macropad_enclosure_iteration1 (Autodesk Fusion 360 design; units mm, degrees)
part number: 2026-10-12-15-45-26-429
Autodesk Fusion 360 part; units mm, degrees
sketch "Upper shell side profile" plane through (0, 0, 0) normal (1, 0, 0) x (0, 0, -1)
  line L0 (-2, 0) -> (-2, 115)
  line L1 (-2, 115) -> (-32.0612, 115)
  line L2 (-32.0612, 115) -> (-22, 0)
  line L3 (-22, 0) -> (-2, 0)
  dimension "d39" = 2
  dimension "d40" = 115
  dimension "d41" = 30.0612
  dimension "d42" = 20
  constraint vertical L0
  constraint horizontal L1
  constraint horizontal L3
  constraint horizontal origin L0.start
  measures "d39" horizontal distance of origin L0.start
  measures "d40" distance of L0.start L0.end
  measures "d41" distance of L0.end L1.end
  measures "d42" distance of L0.start L2.end
extrude "Upper shell wedge" add sketch "Upper shell side profile" along normal blind 80 makes body 1
shell "Open-bottom exterior shell" thickness 2.4 removed faces 1 at (53.3333, 38.3333, 2) on bodies 1
ref_plane "WorkPlane1" through (12.125, 0, 0) normal (0, -0.087156, 0.996195) x (1, 0, 0)
ref_plane "WorkPlane2" through (12.125, -1.9101, 21.8329) normal (0, -0.087156, 0.996195) x (1, 0, 0)
ref_plane "WorkPlane3" through (12.125, -1.6661, 19.0435) normal (0, -0.087156, 0.996195) x (1, 0, 0)
sketch "Middle carrier outline" plane through (0, -1.6661, 19.0435) normal (0, -0.087156, 0.996195) x (1, 0, 0)
  line L0 (2.8, 4.4832) -> (77.2, 4.4832)
  line L1 (77.2, 4.4832) -> (77.2, 114.1698)
  line L2 (77.2, 114.1698) -> (2.8, 114.1698)
  line L3 (2.8, 114.1698) -> (2.8, 4.4832)
  dimension "d52" = 2.8
  dimension "d53" = 4.4832
  dimension "d54" = 74.4
  dimension "d55" = 109.6867
  constraint horizontal L0
  constraint vertical L1
  constraint horizontal L2
  constraint vertical L3
  measures "d52" horizontal distance of origin L0.start
  measures "d53" vertical distance of origin L0.start
  measures "d54" distance of L0.start L0.end
  measures "d55" distance of L0.end L1.end
extrude "Middle carrier plate" add sketch "Middle carrier outline" against normal blind 1.5 separate body makes body 2
sketch "Carrier rear access opening" plane through (0, -1.6661, 19.0435) normal (0, -0.087156, 0.996195) x (1, 0, 0)
  line L0 (6.8, 62.6371) -> (73.2, 62.6371)
  line L1 (73.2, 62.6371) -> (73.2, 110.1698)
  line L2 (73.2, 110.1698) -> (6.8, 110.1698)
  line L3 (6.8, 110.1698) -> (6.8, 62.6371)
  dimension "d58" = 6.8
  dimension "d59" = 62.6371
  dimension "d60" = 66.4
  dimension "d61" = 47.5327
  constraint horizontal L0
  constraint vertical L1
  constraint horizontal L2
  constraint vertical L3
  measures "d58" horizontal distance of origin L0.start
  measures "d59" vertical distance of origin L0.start
  measures "d60" distance of L0.start L0.end
  measures "d61" distance of L0.end L1.end
extrude "Open carrier electronics bay" cut sketch "Carrier rear access opening" against normal blind 2.5 bodies 2
sketch "SW1 Seat profile" plane through (0, -1.6661, 19.0435) normal (0, -0.087156, 0.996195) x (1, 0, 0)
  line L0 (8.45, 18.8371) -> (22.55, 18.8371)
  line L1 (22.55, 18.8371) -> (22.55, 32.9371)
  line L2 (22.55, 32.9371) -> (8.45, 32.9371)
  line L3 (8.45, 32.9371) -> (8.45, 18.8371)
  dimension "d64" = 8.45
  dimension "d65" = 18.8371
  dimension "d66" = 14.1
  dimension "d67" = 14.1
  constraint horizontal L0
  constraint vertical L1
  constraint horizontal L2
  constraint vertical L3
  measures "d64" horizontal distance of origin L0.start
  measures "d65" vertical distance of origin L0.start
  measures "d66" distance of L0.start L0.end
  measures "d67" distance of L0.end L1.end
extrude "SW1 Seat opening" cut sketch "SW1 Seat profile" against normal blind 2.5 bodies 2
sketch "SW1 Trim profile" plane through (0, -1.9101, 21.8329) normal (0, -0.087156, 0.996195) x (1, 0, 0)
  line L0 (7.4, 17.7871) -> (23.6, 17.7871)
  line L1 (23.6, 17.7871) -> (23.6, 33.9871)
  line L2 (23.6, 33.9871) -> (7.4, 33.9871)
  line L3 (7.4, 33.9871) -> (7.4, 17.7871)
  dimension "d70" = 7.4
  dimension "d71" = 17.7871
  dimension "d72" = 16.2
  dimension "d73" = 16.2
  constraint horizontal L0
  constraint vertical L1
  constraint horizontal L2
  constraint vertical L3
  measures "d70" horizontal distance of origin L0.start
  measures "d71" vertical distance of origin L0.start
  measures "d72" distance of L0.start L0.end
  measures "d73" distance of L0.end L1.end
extrude "SW1 Trim opening" cut sketch "SW1 Trim profile" against normal blind 3.4 bodies 1
sketch "SW2 Seat profile" plane through (0, -1.6661, 19.0435) normal (0, -0.087156, 0.996195) x (1, 0, 0)
  line L0 (32.95, 18.8371) -> (47.05, 18.8371)
  line L1 (47.05, 18.8371) -> (47.05, 32.9371)
  line L2 (47.05, 32.9371) -> (32.95, 32.9371)
  line L3 (32.95, 32.9371) -> (32.95, 18.8371)
  dimension "d76" = 32.95
  dimension "d77" = 18.8371
  dimension "d78" = 14.1
  dimension "d79" = 14.1
  constraint horizontal L0
  constraint vertical L1
  constraint horizontal L2
  constraint vertical L3
  measures "d76" horizontal distance of origin L0.start
  measures "d77" vertical distance of origin L0.start
  measures "d78" distance of L0.start L0.end
  measures "d79" distance of L0.end L1.end
extrude "SW2 Seat opening" cut sketch "SW2 Seat profile" against normal blind 2.5 bodies 2
sketch "SW2 Trim profile" plane through (0, -1.9101, 21.8329) normal (0, -0.087156, 0.996195) x (1, 0, 0)
  line L0 (31.9, 17.7871) -> (48.1, 17.7871)
  line L1 (48.1, 17.7871) -> (48.1, 33.9871)
  line L2 (48.1, 33.9871) -> (31.9, 33.9871)
  line L3 (31.9, 33.9871) -> (31.9, 17.7871)
  dimension "d82" = 31.9
  dimension "d83" = 17.7871
  dimension "d84" = 16.2
  dimension "d85" = 16.2
  constraint horizontal L0
  constraint vertical L1
  constraint horizontal L2
  constraint vertical L3
  measures "d82" horizontal distance of origin L0.start
  measures "d83" vertical distance of origin L0.start
  measures "d84" distance of L0.start L0.end
  measures "d85" distance of L0.end L1.end
extrude "SW2 Trim opening" cut sketch "SW2 Trim profile" against normal blind 3.4 bodies 1
sketch "SW3 Seat profile" plane through (0, -1.6661, 19.0435) normal (0, -0.087156, 0.996195) x (1, 0, 0)
  line L0 (57.45, 18.8371) -> (71.55, 18.8371)
  line L1 (71.55, 18.8371) -> (71.55, 32.9371)
  line L2 (71.55, 32.9371) -> (57.45, 32.9371)
  line L3 (57.45, 32.9371) -> (57.45, 18.8371)
  dimension "d88" = 57.45
  dimension "d89" = 18.8371
  dimension "d90" = 14.1
  dimension "d91" = 14.1
  constraint horizontal L0
  constraint vertical L1
  constraint horizontal L2
  constraint vertical L3
  measures "d88" horizontal distance of origin L0.start
  measures "d89" vertical distance of origin L0.start
  measures "d90" distance of L0.start L0.end
  measures "d91" distance of L0.end L1.end
extrude "SW3 Seat opening" cut sketch "SW3 Seat profile" against normal blind 2.5 bodies 2
sketch "SW3 Trim profile" plane through (0, -1.9101, 21.8329) normal (0, -0.087156, 0.996195) x (1, 0, 0)
  line L0 (56.4, 17.7871) -> (72.6, 17.7871)
  line L1 (72.6, 17.7871) -> (72.6, 33.9871)
  line L2 (72.6, 33.9871) -> (56.4, 33.9871)
  line L3 (56.4, 33.9871) -> (56.4, 17.7871)
  dimension "d94" = 56.4
  dimension "d95" = 17.7871
  dimension "d96" = 16.2
  dimension "d97" = 16.2
  constraint horizontal L0
  constraint vertical L1
  constraint horizontal L2
  constraint vertical L3
  measures "d94" horizontal distance of origin L0.start
  measures "d95" vertical distance of origin L0.start
  measures "d96" distance of L0.start L0.end
  measures "d97" distance of L0.end L1.end
extrude "SW3 Trim opening" cut sketch "SW3 Trim profile" against normal blind 3.4 bodies 1
sketch "SW4 Seat profile" plane through (0, -1.6661, 19.0435) normal (0, -0.087156, 0.996195) x (1, 0, 0)
  line L0 (8.45, 43.3371) -> (22.55, 43.3371)
  line L1 (22.55, 43.3371) -> (22.55, 57.4371)
  line L2 (22.55, 57.4371) -> (8.45, 57.4371)
  line L3 (8.45, 57.4371) -> (8.45, 43.3371)
  dimension "d100" = 8.45
  dimension "d101" = 43.3371
  dimension "d102" = 14.1
  dimension "d103" = 14.1
  constraint horizontal L0
  constraint vertical L1
  constraint horizontal L2
  constraint vertical L3
  measures "d100" horizontal distance of origin L0.start
  measures "d101" vertical distance of origin L0.start
  measures "d102" distance of L0.start L0.end
  measures "d103" distance of L0.end L1.end
extrude "SW4 Seat opening" cut sketch "SW4 Seat profile" against normal blind 2.5 bodies 2
sketch "SW4 Trim profile" plane through (0, -1.9101, 21.8329) normal (0, -0.087156, 0.996195) x (1, 0, 0)
  line L0 (7.4, 42.2871) -> (23.6, 42.2871)
  line L1 (23.6, 42.2871) -> (23.6, 58.4871)
  line L2 (23.6, 58.4871) -> (7.4, 58.4871)
  line L3 (7.4, 58.4871) -> (7.4, 42.2871)
  dimension "d106" = 7.4
  dimension "d107" = 42.2871
  dimension "d108" = 16.2
  dimension "d109" = 16.2
  constraint horizontal L0
  constraint vertical L1
  constraint horizontal L2
  constraint vertical L3
  measures "d106" horizontal distance of origin L0.start
  measures "d107" vertical distance of origin L0.start
  measures "d108" distance of L0.start L0.end
  measures "d109" distance of L0.end L1.end
extrude "SW4 Trim opening" cut sketch "SW4 Trim profile" against normal blind 3.4 bodies 1
sketch "SW5 Seat profile" plane through (0, -1.6661, 19.0435) normal (0, -0.087156, 0.996195) x (1, 0, 0)
  line L0 (32.95, 43.3371) -> (47.05, 43.3371)
  line L1 (47.05, 43.3371) -> (47.05, 57.4371)
  line L2 (47.05, 57.4371) -> (32.95, 57.4371)
  line L3 (32.95, 57.4371) -> (32.95, 43.3371)
  dimension "d112" = 32.95
  dimension "d113" = 43.3371
  dimension "d114" = 14.1
  dimension "d115" = 14.1
  constraint horizontal L0
  constraint vertical L1
  constraint horizontal L2
  constraint vertical L3
  measures "d112" horizontal distance of origin L0.start
  measures "d113" vertical distance of origin L0.start
  measures "d114" distance of L0.start L0.end
  measures "d115" distance of L0.end L1.end
extrude "SW5 Seat opening" cut sketch "SW5 Seat profile" against normal blind 2.5 bodies 2
sketch "SW5 Trim profile" plane through (0, -1.9101, 21.8329) normal (0, -0.087156, 0.996195) x (1, 0, 0)
  line L0 (31.9, 42.2871) -> (48.1, 42.2871)
  line L1 (48.1, 42.2871) -> (48.1, 58.4871)
  line L2 (48.1, 58.4871) -> (31.9, 58.4871)
  line L3 (31.9, 58.4871) -> (31.9, 42.2871)
  dimension "d118" = 31.9
  dimension "d119" = 42.2871
  dimension "d120" = 16.2
  dimension "d121" = 16.2
  constraint horizontal L0
  constraint vertical L1
  constraint horizontal L2
  constraint vertical L3
  measures "d118" horizontal distance of origin L0.start
  measures "d119" vertical distance of origin L0.start
  measures "d120" distance of L0.start L0.end
  measures "d121" distance of L0.end L1.end
extrude "SW5 Trim opening" cut sketch "SW5 Trim profile" against normal blind 3.4 bodies 1
sketch "SW6 Seat profile" plane through (0, -1.6661, 19.0435) normal (0, -0.087156, 0.996195) x (1, 0, 0)
  line L0 (57.45, 43.3371) -> (71.55, 43.3371)
  line L1 (71.55, 43.3371) -> (71.55, 57.4371)
  line L2 (71.55, 57.4371) -> (57.45, 57.4371)
  line L3 (57.45, 57.4371) -> (57.45, 43.3371)
  dimension "d124" = 57.45
  dimension "d125" = 43.3371
  dimension "d126" = 14.1
  dimension "d127" = 14.1
  constraint horizontal L0
  constraint vertical L1
  constraint horizontal L2
  constraint vertical L3
  measures "d124" horizontal distance of origin L0.start
  measures "d125" vertical distance of origin L0.start
  measures "d126" distance of L0.start L0.end
  measures "d127" distance of L0.end L1.end
extrude "SW6 Seat opening" cut sketch "SW6 Seat profile" against normal blind 2.5 bodies 2
sketch "SW6 Trim profile" plane through (0, -1.9101, 21.8329) normal (0, -0.087156, 0.996195) x (1, 0, 0)
  line L0 (56.4, 42.2871) -> (72.6, 42.2871)
  line L1 (72.6, 42.2871) -> (72.6, 58.4871)
  line L2 (72.6, 58.4871) -> (56.4, 58.4871)
  line L3 (56.4, 58.4871) -> (56.4, 42.2871)
  dimension "d130" = 56.4
  dimension "d131" = 42.2871
  dimension "d132" = 16.2
  dimension "d133" = 16.2
  constraint horizontal L0
  constraint vertical L1
  constraint horizontal L2
  constraint vertical L3
  measures "d130" horizontal distance of origin L0.start
  measures "d131" vertical distance of origin L0.start
  measures "d132" distance of L0.start L0.end
  measures "d133" distance of L0.end L1.end
extrude "SW6 Trim opening" cut sketch "SW6 Trim profile" against normal blind 3.4 bodies 1
sketch "LED diffuser opening profile" plane through (0, -1.9101, 21.8329) normal (0, -0.087156, 0.996195) x (1, 0, 0)
  line L0 (6.5, 92.3871) -> (73.5, 92.3871)
  line L1 (73.5, 92.3871) -> (73.5, 102.3871)
  line L2 (73.5, 102.3871) -> (6.5, 102.3871)
  line L3 (6.5, 102.3871) -> (6.5, 92.3871)
  dimension "d136" = 6.5
  dimension "d137" = 92.3871
  dimension "d138" = 67
  dimension "d139" = 10
  constraint horizontal L0
  constraint vertical L1
  constraint horizontal L2
  constraint vertical L3
  measures "d136" horizontal distance of origin L0.start
  measures "d137" vertical distance of origin L0.start
  measures "d138" distance of L0.start L0.end
  measures "d139" distance of L0.end L1.end
extrude "LED diffuser opening" cut sketch "LED diffuser opening profile" against normal blind 3.4 bodies 1
sketch "OLED window profile" plane through (0, -1.9101, 21.8329) normal (0, -0.087156, 0.996195) x (1, 0, 0)
  line L0 (6.5, 66.6371) -> (41, 66.6371)
  line L1 (41, 66.6371) -> (41, 85.1371)
  line L2 (41, 85.1371) -> (6.5, 85.1371)
  line L3 (6.5, 85.1371) -> (6.5, 66.6371)
  dimension "d142" = 6.5
  dimension "d143" = 66.6371
  dimension "d145" = 18.5
  constraint horizontal L0
  constraint vertical L1
  constraint horizontal L2
  constraint vertical L3
  measures "d142" horizontal distance of origin L0.start
  measures "d143" vertical distance of origin L0.start
  measures "d145" distance of L0.end L1.end
extrude "OLED window" cut sketch "OLED window profile" against normal blind 3.4 bodies 1
sketch "Encoder provisional bushing profile" plane through (0, -1.9101, 21.8329) normal (0, -0.087156, 0.996195) x (1, 0, 0)
  circle A0 centre (60.5, 75.8871) radius 3.5
  dimension "d148" = 60.5
  dimension "d149" = 75.8871
  dimension "d150" = 7
  measures "d148" horizontal distance of origin A0.centre
  measures "d149" vertical distance of origin A0.centre
  measures "d150" diameter of A0
extrude "Encoder provisional opening" cut sketch "Encoder provisional bushing profile" against normal blind 3.4 bodies 1
sketch "Bottom cover outline" plane through (0, 0, 0) normal (0, 0, 1) x (1, 0, 0)
  line L0 (0, 0) -> (80, 0)
  line L1 (80, 0) -> (80, 115)
  line L2 (80, 115) -> (0, 115)
  line L3 (0, 115) -> (0, 0)
  dimension "d153" = 80
  dimension "d154" = 115
  constraint horizontal L0
  constraint vertical L1
  constraint horizontal L2
  constraint vertical L3
  constraint coincident L0.start L3.end
  measures "d153" distance of L0.start L0.end
  measures "d154" distance of L0.end L1.end
extrude "Bottom service cover" add sketch "Bottom cover outline" along normal blind 2 separate body makes body 3
sketch "Diffuser flush plug profile" plane through (0, -1.9101, 21.8329) normal (0, -0.087156, 0.996195) x (1, 0, 0)
  line L0 (6.7, 92.5871) -> (73.3, 92.5871)
  line L1 (73.3, 92.5871) -> (73.3, 102.1871)
  line L2 (73.3, 102.1871) -> (6.7, 102.1871)
  line L3 (6.7, 102.1871) -> (6.7, 92.5871)
  dimension "d157" = 6.7
  dimension "d158" = 92.5871
  dimension "d159" = 66.6
  dimension "d160" = 9.6
  constraint horizontal L0
  constraint vertical L1
  constraint horizontal L2
  constraint vertical L3
  measures "d157" horizontal distance of origin L0.start
  measures "d158" vertical distance of origin L0.start
  measures "d159" distance of L0.start L0.end
  measures "d160" distance of L0.end L1.end
extrude "Diffuser flush plug" add sketch "Diffuser flush plug profile" against normal blind 2.4 separate body makes body 4
ref_plane "WorkPlane4" through (12.125, -1.701, 19.442) normal (0, -0.087156, 0.996195) x (1, 0, 0)
sketch "Diffuser retaining flange profile" plane through (0, -1.701, 19.442) normal (0, -0.087156, 0.996195) x (1, 0, 0)
  line L0 (5.2, 91.0871) -> (74.8, 91.0871)
  line L1 (74.8, 91.0871) -> (74.8, 103.6871)
  line L2 (74.8, 103.6871) -> (5.2, 103.6871)
  line L3 (5.2, 103.6871) -> (5.2, 91.0871)
  dimension "d165" = 5.2
  dimension "d166" = 91.0871
  dimension "d167" = 69.6
  dimension "d168" = 12.6
  constraint horizontal L0
  constraint vertical L1
  constraint horizontal L2
  constraint vertical L3
  measures "d165" horizontal distance of origin L0.start
  measures "d166" vertical distance of origin L0.start
  measures "d167" distance of L0.start L0.end
  measures "d168" distance of L0.end L1.end
extrude "Diffuser retaining flange" add sketch "Diffuser retaining flange profile" against normal blind 1 bodies 4
sketch "SW1 keycap envelope" plane through (0, -1.9101, 21.8329) normal (0, -0.087156, 0.996195) x (1, 0, 0)
  line L0 (6.5, 16.8871) -> (24.5, 16.8871) construction
  line L1 (24.5, 16.8871) -> (24.5, 34.8871) construction
  line L2 (24.5, 34.8871) -> (6.5, 34.8871) construction
  line L3 (6.5, 34.8871) -> (6.5, 16.8871) construction
  dimension "d172" = 6.5
  dimension "d173" = 16.8871
  dimension "d174" = 18
  dimension "d175" = 18
  constraint horizontal L0
  constraint vertical L1
  constraint horizontal L2
  constraint vertical L3
  measures "d172" horizontal distance of origin L0.start
  measures "d173" vertical distance of origin L0.start
  measures "d174" distance of L0.start L0.end
  measures "d175" distance of L0.end L1.end
sketch "SW2 keycap envelope" plane through (0, -1.9101, 21.8329) normal (0, -0.087156, 0.996195) x (1, 0, 0)
  line L0 (31, 16.8871) -> (49, 16.8871) construction
  line L1 (49, 16.8871) -> (49, 34.8871) construction
  line L2 (49, 34.8871) -> (31, 34.8871) construction
  line L3 (31, 34.8871) -> (31, 16.8871) construction
  dimension "d176" = 31
  dimension "d177" = 16.8871
  dimension "d178" = 18
  dimension "d179" = 18
  constraint horizontal L0
  constraint vertical L1
  constraint horizontal L2
  constraint vertical L3
  measures "d176" horizontal distance of origin L0.start
  measures "d177" vertical distance of origin L0.start
  measures "d178" distance of L0.start L0.end
  measures "d179" distance of L0.end L1.end
sketch "SW3 keycap envelope" plane through (0, -1.9101, 21.8329) normal (0, -0.087156, 0.996195) x (1, 0, 0)
  line L0 (55.5, 16.8871) -> (73.5, 16.8871) construction
  line L1 (73.5, 16.8871) -> (73.5, 34.8871) construction
  line L2 (73.5, 34.8871) -> (55.5, 34.8871) construction
  line L3 (55.5, 34.8871) -> (55.5, 16.8871) construction
  dimension "d180" = 55.5
  dimension "d181" = 16.8871
  dimension "d182" = 18
  dimension "d183" = 18
  constraint horizontal L0
  constraint vertical L1
  constraint horizontal L2
  constraint vertical L3
  measures "d180" horizontal distance of origin L0.start
  measures "d181" vertical distance of origin L0.start
  measures "d182" distance of L0.start L0.end
  measures "d183" distance of L0.end L1.end
sketch "SW4 keycap envelope" plane through (0, -1.9101, 21.8329) normal (0, -0.087156, 0.996195) x (1, 0, 0)
  line L0 (6.5, 41.3871) -> (24.5, 41.3871) construction
  line L1 (24.5, 41.3871) -> (24.5, 59.3871) construction
  line L2 (24.5, 59.3871) -> (6.5, 59.3871) construction
  line L3 (6.5, 59.3871) -> (6.5, 41.3871) construction
  dimension "d184" = 6.5
  dimension "d185" = 41.3871
  dimension "d186" = 18
  dimension "d187" = 18
  constraint horizontal L0
  constraint vertical L1
  constraint horizontal L2
  constraint vertical L3
  measures "d184" horizontal distance of origin L0.start
  measures "d185" vertical distance of origin L0.start
  measures "d186" distance of L0.start L0.end
  measures "d187" distance of L0.end L1.end
sketch "SW5 keycap envelope" plane through (0, -1.9101, 21.8329) normal (0, -0.087156, 0.996195) x (1, 0, 0)
  line L0 (31, 41.3871) -> (49, 41.3871) construction
  line L1 (49, 41.3871) -> (49, 59.3871) construction
  line L2 (49, 59.3871) -> (31, 59.3871) construction
  line L3 (31, 59.3871) -> (31, 41.3871) construction
  dimension "d188" = 31
  dimension "d189" = 41.3871
  dimension "d190" = 18
  dimension "d191" = 18
  constraint horizontal L0
  constraint vertical L1
  constraint horizontal L2
  constraint vertical L3
  measures "d188" horizontal distance of origin L0.start
  measures "d189" vertical distance of origin L0.start
  measures "d190" distance of L0.start L0.end
  measures "d191" distance of L0.end L1.end
sketch "SW6 keycap envelope" plane through (0, -1.9101, 21.8329) normal (0, -0.087156, 0.996195) x (1, 0, 0)
  line L0 (55.5, 41.3871) -> (73.5, 41.3871) construction
  line L1 (73.5, 41.3871) -> (73.5, 59.3871) construction
  line L2 (73.5, 59.3871) -> (55.5, 59.3871) construction
  line L3 (55.5, 59.3871) -> (55.5, 41.3871) construction
  dimension "d192" = 55.5
  dimension "d193" = 41.3871
  dimension "d194" = 18
  dimension "d195" = 18
  constraint horizontal L0
  constraint vertical L1
  constraint horizontal L2
  constraint vertical L3
  measures "d192" horizontal distance of origin L0.start
  measures "d193" vertical distance of origin L0.start
  measures "d194" distance of L0.start L0.end
  measures "d195" distance of L0.end L1.end
sketch "Encoder knob envelope - provisional diameter" plane through (0, -1.9101, 21.8329) normal (0, -0.087156, 0.996195) x (1, 0, 0)
  circle A0 centre (60.5, 75.8871) radius 10 construction
  dimension "d196" = 60.5
  dimension "d197" = 75.8871
  dimension "d198" = 20
  measures "d196" horizontal distance of origin A0.centre
  measures "d197" vertical distance of origin A0.centre
  measures "d198" diameter of A0
sketch "Diffuser flange carrier pocket profile" plane through (0, -1.6661, 19.0435) normal (0, -0.087156, 0.996195) x (1, 0, 0)
  line L0 (5, 90.8871) -> (75, 90.8871)
  line L1 (75, 90.8871) -> (75, 103.8871)
  line L2 (75, 103.8871) -> (5, 103.8871)
  line L3 (5, 103.8871) -> (5, 90.8871)
  dimension "d200" = 5
  dimension "d201" = 90.8871
  dimension "d202" = 70
  dimension "d203" = 13
  constraint horizontal L0
  constraint vertical L1
  constraint horizontal L2
  constraint vertical L3
  measures "d200" horizontal distance of origin L0.start
  measures "d201" vertical distance of origin L0.start
  measures "d202" distance of L0.start L0.end
  measures "d203" distance of L0.end L1.end
extrude "Diffuser flange carrier recess" cut sketch "Diffuser flange carrier pocket profile" against normal blind 0.8 bodies 2
hidden bodies 1 3
equation "caseWidth = 80 mm" comment "Exterior width"
equation "caseLength = 115 mm" comment "Horizontal front-to-rear footprint"
equation "caseTilt = 5 deg" comment "Rear-up face angle; provisional"
equation "frontHeight = 22 mm" comment "Draft height, to be checked against electronics"
equation "rearHeight = frontHeight + caseLength * tan(caseTilt)" comment "Rear height"
equation "shellWall = 2.4 mm" comment "Draft shell thickness"
equation "bottomThickness = 2 mm" comment "Service cover thickness"
equation "carrierThickness = 1.5 mm" comment "Local switch clip seating thickness"
equation "carrierClearance = 0.4 mm" comment "Draft carrier clearance"
equation "carrierRim = 4 mm" comment "Carrier frame width"
equation "keycapSize = 18 mm" comment "Confirmed square keycap size"
equation "layoutGap = ( caseWidth - 3 * keycapSize ) / 4" comment "Equal visible horizontal gaps"
equation "keyPitch = keycapSize + layoutGap" comment "Equal row and column pitch"
equation "switchOpening = 14.1 mm" comment "Draft opening; coupon verification required"
equation "upperSwitchOpening = 16.2 mm" comment "Draft outer trim clearance"
equation "displayWidth = 34.5 mm" comment "User-supplied window width"
equation "displayHeight = 18.5 mm" comment "User-supplied window height"
equation "encoderKnobDiameter = 20 mm" comment "Placeholder; actual knob diameter required"
equation "encoderHole = 7 mm" comment "User-supplied provisional opening; verify bushing"
equation "ledWidth = 67 mm" comment "User-supplied strip width"
equation "ledHeight = 10 mm" comment "Initial diffuser opening height"
equation "diffuserClearance = 0.2 mm" comment "Per-edge draft fit clearance"
equation "diffuserFlange = 1.5 mm" comment "Retaining flange extension per side"
equation "diffuserFlangeThickness = 1 mm" comment "Retaining flange thickness"
equation "faceLength = caseLength / cos(caseTilt)" comment "Length measured in the inclined face"
equation "faceOriginV = frontHeight * sin(caseTilt)" comment "Inclined sketch origin correction"
equation "controlHeight = max(displayHeight; encoderKnobDiameter)" comment "Visible controls row height"
equation "contentLength = 2 * keycapSize + 3 * layoutGap + controlHeight + ledHeight" comment "Visible layout stack"
equation "verticalMargin = ( faceLength - contentLength ) / 2" comment "Balanced front and rear margins"
equation "keyRowOne = verticalMargin + keycapSize / 2" comment "Front key row center"
equation "keyRowTwo = keyRowOne + keyPitch" comment "Rear key row center"
equation "controlCenter = keyRowTwo + keycapSize / 2 + layoutGap + controlHeight / 2" comment "Display and encoder center"
equation "ledCenter = controlCenter + controlHeight / 2 + layoutGap + ledHeight / 2" comment "LED opening center"
equation "encoderCenterX = ( layoutGap + displayWidth + caseWidth ) / 2" comment "Centered in the area right of the display"
equation "d39 = -( ( 0 ) * ( 0 mm ) + ( -1 ) * ( bottomThickness ) )"
equation "d40 = ( ( 1 ) * ( caseLength ) + ( 0 ) * ( bottomThickness ) ) - ( ( 1 ) * ( 0 mm ) + ( 0 ) * ( bottomThickness ) )"
equation "d41 = -( ( ( 0 ) * ( caseLength ) + ( -1 ) * ( rearHeight ) ) - ( ( 0 ) * ( caseLength ) + ( -1 ) * ( bottomThickness ) ) )"
equation "d42 = ( ( 0 ) * ( 0 mm ) + ( -1 ) * ( bottomThickness ) ) - ( ( 0 ) * ( 0 mm ) + ( -1 ) * ( frontHeight ) )"
equation "d43 = caseWidth"
equation "d45 = shellWall"
equation "d46 = caseTilt"
equation "d48 = frontHeight * cos(caseTilt)"
equation "d50 = -( shellWall + carrierClearance )"
equation "d52 = shellWall + carrierClearance"
equation "d53 = ( ( shellWall + carrierClearance ) / cos(caseTilt) - ( shellWall + carrierClearance ) * tan(caseTilt) ) + faceOriginV"
equation "d54 = ( ( shellWall + carrierClearance ) + ( caseWidth - 2 * ( shellWall + carrierClearance ) ) ) - ( shellWall + carrierClearance )"
equation "d55 = carrierFaceLength"
equation "d56 = -( carrierThickness )"
equation "d58 = ( caseWidth - carrierBayWidth ) / 2"
equation "d59 = ( keyRowTwo + keycapSize / 2 + layoutGap / 2 ) + faceOriginV"
equation "d60 = carrierBayWidth"
equation "d61 = faceLength - ( shellWall + carrierClearance ) / cos(caseTilt) - ( shellWall + carrierClearance + carrierThickness ) * tan(caseTilt) - carrierRim - ( keyRowTwo + keycapSize / 2 + layoutGap / 2 )"
equation "d62 = -( carrierThickness + 1 mm )"
equation "d64 = ( layoutGap + keycapSize / 2 + 0 * keyPitch ) - switchOpening / 2"
equation "d65 = ( ( keyRowOne ) - switchOpening / 2 ) + faceOriginV"
equation "d66 = ( ( ( layoutGap + keycapSize / 2 + 0 * keyPitch ) - switchOpening / 2 ) + ( switchOpening ) ) - ( ( layoutGap + keycapSize / 2 + 0 * keyPitch ) - switchOpening / 2 )"
equation "d67 = ( ( ( ( keyRowOne ) - switchOpening / 2 ) + faceOriginV ) + ( switchOpening ) ) - ( ( ( keyRowOne ) - switchOpening / 2 ) + faceOriginV )"
equation "d68 = -( carrierThickness + 1 mm )"
equation "d70 = ( layoutGap + keycapSize / 2 + 0 * keyPitch ) - upperSwitchOpening / 2"
equation "d71 = ( ( keyRowOne ) - upperSwitchOpening / 2 ) + faceOriginV"
equation "d72 = ( ( ( layoutGap + keycapSize / 2 + 0 * keyPitch ) - upperSwitchOpening / 2 ) + ( upperSwitchOpening ) ) - ( ( layoutGap + keycapSize / 2 + 0 * keyPitch ) - upperSwitchOpening / 2 )"
equation "d73 = ( ( ( ( keyRowOne ) - upperSwitchOpening / 2 ) + faceOriginV ) + ( upperSwitchOpening ) ) - ( ( ( keyRowOne ) - upperSwitchOpening / 2 ) + faceOriginV )"
equation "d74 = -( shellWall + 1 mm )"
equation "d76 = ( layoutGap + keycapSize / 2 + 1 * keyPitch ) - switchOpening / 2"
equation "d77 = ( ( keyRowOne ) - switchOpening / 2 ) + faceOriginV"
equation "d78 = ( ( ( layoutGap + keycapSize / 2 + 1 * keyPitch ) - switchOpening / 2 ) + ( switchOpening ) ) - ( ( layoutGap + keycapSize / 2 + 1 * keyPitch ) - switchOpening / 2 )"
equation "d79 = ( ( ( ( keyRowOne ) - switchOpening / 2 ) + faceOriginV ) + ( switchOpening ) ) - ( ( ( keyRowOne ) - switchOpening / 2 ) + faceOriginV )"
equation "d80 = -( carrierThickness + 1 mm )"
equation "d82 = ( layoutGap + keycapSize / 2 + 1 * keyPitch ) - upperSwitchOpening / 2"
equation "d83 = ( ( keyRowOne ) - upperSwitchOpening / 2 ) + faceOriginV"
equation "d84 = ( ( ( layoutGap + keycapSize / 2 + 1 * keyPitch ) - upperSwitchOpening / 2 ) + ( upperSwitchOpening ) ) - ( ( layoutGap + keycapSize / 2 + 1 * keyPitch ) - upperSwitchOpening / 2 )"
equation "d85 = ( ( ( ( keyRowOne ) - upperSwitchOpening / 2 ) + faceOriginV ) + ( upperSwitchOpening ) ) - ( ( ( keyRowOne ) - upperSwitchOpening / 2 ) + faceOriginV )"
equation "d86 = -( shellWall + 1 mm )"
equation "d88 = ( layoutGap + keycapSize / 2 + 2 * keyPitch ) - switchOpening / 2"
equation "d89 = ( ( keyRowOne ) - switchOpening / 2 ) + faceOriginV"
equation "d90 = ( ( ( layoutGap + keycapSize / 2 + 2 * keyPitch ) - switchOpening / 2 ) + ( switchOpening ) ) - ( ( layoutGap + keycapSize / 2 + 2 * keyPitch ) - switchOpening / 2 )"
equation "d91 = ( ( ( ( keyRowOne ) - switchOpening / 2 ) + faceOriginV ) + ( switchOpening ) ) - ( ( ( keyRowOne ) - switchOpening / 2 ) + faceOriginV )"
equation "d92 = -( carrierThickness + 1 mm )"
equation "d94 = ( layoutGap + keycapSize / 2 + 2 * keyPitch ) - upperSwitchOpening / 2"
equation "d95 = ( ( keyRowOne ) - upperSwitchOpening / 2 ) + faceOriginV"
equation "d96 = ( ( ( layoutGap + keycapSize / 2 + 2 * keyPitch ) - upperSwitchOpening / 2 ) + ( upperSwitchOpening ) ) - ( ( layoutGap + keycapSize / 2 + 2 * keyPitch ) - upperSwitchOpening / 2 )"
equation "d97 = ( ( ( ( keyRowOne ) - upperSwitchOpening / 2 ) + faceOriginV ) + ( upperSwitchOpening ) ) - ( ( ( keyRowOne ) - upperSwitchOpening / 2 ) + faceOriginV )"
equation "d98 = -( shellWall + 1 mm )"
equation "d100 = ( layoutGap + keycapSize / 2 + 0 * keyPitch ) - switchOpening / 2"
equation "d101 = ( ( keyRowTwo ) - switchOpening / 2 ) + faceOriginV"
equation "d102 = ( ( ( layoutGap + keycapSize / 2 + 0 * keyPitch ) - switchOpening / 2 ) + ( switchOpening ) ) - ( ( layoutGap + keycapSize / 2 + 0 * keyPitch ) - switchOpening / 2 )"
equation "d103 = ( ( ( ( keyRowTwo ) - switchOpening / 2 ) + faceOriginV ) + ( switchOpening ) ) - ( ( ( keyRowTwo ) - switchOpening / 2 ) + faceOriginV )"
equation "d104 = -( carrierThickness + 1 mm )"
equation "d106 = ( layoutGap + keycapSize / 2 + 0 * keyPitch ) - upperSwitchOpening / 2"
equation "d107 = ( ( keyRowTwo ) - upperSwitchOpening / 2 ) + faceOriginV"
equation "d108 = ( ( ( layoutGap + keycapSize / 2 + 0 * keyPitch ) - upperSwitchOpening / 2 ) + ( upperSwitchOpening ) ) - ( ( layoutGap + keycapSize / 2 + 0 * keyPitch ) - upperSwitchOpening / 2 )"
equation "d109 = ( ( ( ( keyRowTwo ) - upperSwitchOpening / 2 ) + faceOriginV ) + ( upperSwitchOpening ) ) - ( ( ( keyRowTwo ) - upperSwitchOpening / 2 ) + faceOriginV )"
equation "d110 = -( shellWall + 1 mm )"
equation "d112 = ( layoutGap + keycapSize / 2 + 1 * keyPitch ) - switchOpening / 2"
equation "d113 = ( ( keyRowTwo ) - switchOpening / 2 ) + faceOriginV"
equation "d114 = ( ( ( layoutGap + keycapSize / 2 + 1 * keyPitch ) - switchOpening / 2 ) + ( switchOpening ) ) - ( ( layoutGap + keycapSize / 2 + 1 * keyPitch ) - switchOpening / 2 )"
equation "d115 = ( ( ( ( keyRowTwo ) - switchOpening / 2 ) + faceOriginV ) + ( switchOpening ) ) - ( ( ( keyRowTwo ) - switchOpening / 2 ) + faceOriginV )"
equation "d116 = -( carrierThickness + 1 mm )"
equation "d118 = ( layoutGap + keycapSize / 2 + 1 * keyPitch ) - upperSwitchOpening / 2"
equation "d119 = ( ( keyRowTwo ) - upperSwitchOpening / 2 ) + faceOriginV"
equation "d120 = ( ( ( layoutGap + keycapSize / 2 + 1 * keyPitch ) - upperSwitchOpening / 2 ) + ( upperSwitchOpening ) ) - ( ( layoutGap + keycapSize / 2 + 1 * keyPitch ) - upperSwitchOpening / 2 )"
equation "d121 = ( ( ( ( keyRowTwo ) - upperSwitchOpening / 2 ) + faceOriginV ) + ( upperSwitchOpening ) ) - ( ( ( keyRowTwo ) - upperSwitchOpening / 2 ) + faceOriginV )"
equation "d122 = -( shellWall + 1 mm )"
equation "d124 = ( layoutGap + keycapSize / 2 + 2 * keyPitch ) - switchOpening / 2"
equation "d125 = ( ( keyRowTwo ) - switchOpening / 2 ) + faceOriginV"
equation "d126 = ( ( ( layoutGap + keycapSize / 2 + 2 * keyPitch ) - switchOpening / 2 ) + ( switchOpening ) ) - ( ( layoutGap + keycapSize / 2 + 2 * keyPitch ) - switchOpening / 2 )"
equation "d127 = ( ( ( ( keyRowTwo ) - switchOpening / 2 ) + faceOriginV ) + ( switchOpening ) ) - ( ( ( keyRowTwo ) - switchOpening / 2 ) + faceOriginV )"
equation "d128 = -( carrierThickness + 1 mm )"
equation "d130 = ( layoutGap + keycapSize / 2 + 2 * keyPitch ) - upperSwitchOpening / 2"
equation "d131 = ( ( keyRowTwo ) - upperSwitchOpening / 2 ) + faceOriginV"
equation "d132 = ( ( ( layoutGap + keycapSize / 2 + 2 * keyPitch ) - upperSwitchOpening / 2 ) + ( upperSwitchOpening ) ) - ( ( layoutGap + keycapSize / 2 + 2 * keyPitch ) - upperSwitchOpening / 2 )"
equation "d133 = ( ( ( ( keyRowTwo ) - upperSwitchOpening / 2 ) + faceOriginV ) + ( upperSwitchOpening ) ) - ( ( ( keyRowTwo ) - upperSwitchOpening / 2 ) + faceOriginV )"
equation "d134 = -( shellWall + 1 mm )"
equation "d136 = ( caseWidth - ledWidth ) / 2"
equation "d137 = ( ledCenter - ledHeight / 2 ) + faceOriginV"
equation "d138 = ( ( ( caseWidth - ledWidth ) / 2 ) + ( ledWidth ) ) - ( ( caseWidth - ledWidth ) / 2 )"
equation "d139 = ( ( ( ledCenter - ledHeight / 2 ) + faceOriginV ) + ( ledHeight ) ) - ( ( ledCenter - ledHeight / 2 ) + faceOriginV )"
equation "d140 = -( shellWall + 1 mm )"
equation "d142 = layoutGap"
equation "d143 = ( controlCenter - displayHeight / 2 ) + faceOriginV"
equation "d144 = ( ( layoutGap ) + ( displayWidth ) ) - ( layoutGap )"
equation "d145 = ( ( ( controlCenter - displayHeight / 2 ) + faceOriginV ) + ( displayHeight ) ) - ( ( controlCenter - displayHeight / 2 ) + faceOriginV )"
equation "d146 = -( shellWall + 1 mm )"
equation "d148 = encoderCenterX"
equation "d149 = controlCenter + faceOriginV"
equation "d150 = encoderHole"
equation "d151 = -( shellWall + 1 mm )"
equation "d153 = ( ( 0 mm ) + ( caseWidth ) ) - ( 0 mm )"
equation "d154 = ( ( 0 mm ) + ( caseLength ) ) - ( 0 mm )"
equation "d155 = bottomThickness"
equation "d157 = ( caseWidth - ledWidth ) / 2 + diffuserClearance"
equation "d158 = ( ledCenter - ledHeight / 2 + diffuserClearance ) + faceOriginV"
equation "d159 = ( ( ( caseWidth - ledWidth ) / 2 + diffuserClearance ) + ( ledWidth - 2 * diffuserClearance ) ) - ( ( caseWidth - ledWidth ) / 2 + diffuserClearance )"
equation "d160 = ( ( ( ledCenter - ledHeight / 2 + diffuserClearance ) + faceOriginV ) + ( ledHeight - 2 * diffuserClearance ) ) - ( ( ledCenter - ledHeight / 2 + diffuserClearance ) + faceOriginV )"
equation "d161 = -( shellWall )"
equation "d163 = -shellWall"
equation "d165 = ( caseWidth - ledWidth ) / 2 + diffuserClearance - diffuserFlange"
equation "d166 = ( ledCenter - ledHeight / 2 + diffuserClearance - diffuserFlange ) + faceOriginV"
equation "d167 = ( ( ( caseWidth - ledWidth ) / 2 + diffuserClearance - diffuserFlange ) + ( ledWidth - 2 * diffuserClearance + 2 * diffuserFlange ) ) - ( ( caseWidth - ledWidth ) / 2 + diffuserClearance - diffuserFlange )"
equation "d168 = ( ( ( ledCenter - ledHeight / 2 + diffuserClearance - diffuserFlange ) + faceOriginV ) + ( ledHeight - 2 * diffuserClearance + 2 * diffuserFlange ) ) - ( ( ledCenter - ledHeight / 2 + diffuserClearance - diffuserFlange ) + faceOriginV )"
equation "d169 = -( diffuserFlangeThickness )"
equation "carrierFaceLength = faceLength - 2 * ( shellWall + carrierClearance ) / cos(caseTilt) - carrierThickness * tan(caseTilt)" comment "Carrier rear clearance"
equation "d172 = layoutGap + 0 * keyPitch"
equation "d173 = ( keyRowOne - keycapSize / 2 ) + faceOriginV"
equation "d174 = ( ( layoutGap + 0 * keyPitch ) + ( keycapSize ) ) - ( layoutGap + 0 * keyPitch )"
equation "d175 = ( ( ( keyRowOne - keycapSize / 2 ) + faceOriginV ) + ( keycapSize ) ) - ( ( keyRowOne - keycapSize / 2 ) + faceOriginV )"
equation "d176 = layoutGap + 1 * keyPitch"
equation "d177 = ( keyRowOne - keycapSize / 2 ) + faceOriginV"
equation "d178 = ( ( layoutGap + 1 * keyPitch ) + ( keycapSize ) ) - ( layoutGap + 1 * keyPitch )"
equation "d179 = ( ( ( keyRowOne - keycapSize / 2 ) + faceOriginV ) + ( keycapSize ) ) - ( ( keyRowOne - keycapSize / 2 ) + faceOriginV )"
equation "d180 = layoutGap + 2 * keyPitch"
equation "d181 = ( keyRowOne - keycapSize / 2 ) + faceOriginV"
equation "d182 = ( ( layoutGap + 2 * keyPitch ) + ( keycapSize ) ) - ( layoutGap + 2 * keyPitch )"
equation "d183 = ( ( ( keyRowOne - keycapSize / 2 ) + faceOriginV ) + ( keycapSize ) ) - ( ( keyRowOne - keycapSize / 2 ) + faceOriginV )"
equation "d184 = layoutGap + 0 * keyPitch"
equation "d185 = ( keyRowTwo - keycapSize / 2 ) + faceOriginV"
equation "d186 = ( ( layoutGap + 0 * keyPitch ) + ( keycapSize ) ) - ( layoutGap + 0 * keyPitch )"
equation "d187 = ( ( ( keyRowTwo - keycapSize / 2 ) + faceOriginV ) + ( keycapSize ) ) - ( ( keyRowTwo - keycapSize / 2 ) + faceOriginV )"
equation "d188 = layoutGap + 1 * keyPitch"
equation "d189 = ( keyRowTwo - keycapSize / 2 ) + faceOriginV"
equation "d190 = ( ( layoutGap + 1 * keyPitch ) + ( keycapSize ) ) - ( layoutGap + 1 * keyPitch )"
equation "d191 = ( ( ( keyRowTwo - keycapSize / 2 ) + faceOriginV ) + ( keycapSize ) ) - ( ( keyRowTwo - keycapSize / 2 ) + faceOriginV )"
equation "d192 = layoutGap + 2 * keyPitch"
equation "d193 = ( keyRowTwo - keycapSize / 2 ) + faceOriginV"
equation "d194 = ( ( layoutGap + 2 * keyPitch ) + ( keycapSize ) ) - ( layoutGap + 2 * keyPitch )"
equation "d195 = ( ( ( keyRowTwo - keycapSize / 2 ) + faceOriginV ) + ( keycapSize ) ) - ( ( keyRowTwo - keycapSize / 2 ) + faceOriginV )"
equation "d196 = encoderCenterX"
equation "d197 = controlCenter + faceOriginV"
equation "d198 = encoderKnobDiameter"
equation "flangePocketClearance = 0.2 mm" comment "Carrier pocket clearance"
equation "d200 = ( caseWidth - ledWidth ) / 2 + diffuserClearance - diffuserFlange - flangePocketClearance"
equation "d201 = ( ledCenter - ledHeight / 2 + diffuserClearance - diffuserFlange - flangePocketClearance ) + faceOriginV"
equation "d202 = ( ( ( caseWidth - ledWidth ) / 2 + diffuserClearance - diffuserFlange - flangePocketClearance ) + ( ledWidth - 2 * diffuserClearance + 2 * diffuserFlange + 2 * flangePocketClearance ) ) - ( ( caseWidth - ledWidth ) / 2 + diffuserClearance - diffuserFlange - flangePocketClearance )"
equation "d203 = ( ( ( ledCenter - ledHeight / 2 + diffuserClearance - diffuserFlange - flangePocketClearance ) + faceOriginV ) + ( ledHeight - 2 * diffuserClearance + 2 * diffuserFlange + 2 * flangePocketClearance ) ) - ( ( ledCenter - ledHeight / 2 + diffuserClearance - diffuserFlange - flangePocketClearance ) + faceOriginV )"
equation "d204 = -( diffuserFlangeThickness - carrierClearance + flangePocketClearance )"
equation "carrierBayWidth = min(caseWidth - 2 * ( shellWall + carrierClearance + carrierRim ); ledWidth - 2 * diffuserClearance + 2 * diffuserFlange - 2 mm)" comment "Electronics opening preserving diffuser support rails"
named bodies: "UpperShell_Draft", "MiddleCarrier_Draft", "BottomCover_Draft", "Diffuser_Draft"
